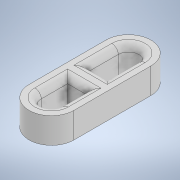
# Autodesk Inventor part: balama_v1
Saved by Autodesk Inventor 2022.6 (Build 266554000, 554)
## iProperties
Created: 2025-08-06
Part Number: balama_v1
Material: Generic
Document SubType Name: Modeling
Designer: Dragos Macovei
Density: 1 g/cm^3
Appearance: Default
Author: Dragos Macovei
Autodesk Inventor part; units mm, degrees
ref_plane "YZ Plane" through (0, 0, 0) normal (1, 0, 0) x (0, 1, 0)
ref_plane "XZ Plane" through (0, 0, 0) normal (0, 1, 0) x (-1, 0, 0)
ref_plane "XY Plane" through (0, 0, 0) normal (0, 0, 1) x (1, 0, 0)
sketch "Sketch1" plane through (0, 0, 0) normal (0, 1, 0) x (-1, 0, 0)
  circle A0 centre (0, 0) radius 1.6
  circle A1 centre (0, -12) radius 1.6
  arc A2 (3.5, 0) -> (-3.5, 0) centre (0, 0) ccw
  arc A3 (-3.5, -12) -> (3.5, -12) centre (0, -12) ccw
  line L0 (3.5, 0) -> (3.5, -12)
  line L1 (-3.5, 0) -> (-3.5, -12)
  dimension "d0" = 3.2
  dimension "d1" = 3.2
  dimension "d2" = 7
  dimension "d3" = 7
  dimension "d4" = 12
  constraints: 4 centre point, 4 end point, 4 point on circle, 3 coincident, 1 parallel, 1 tangent
  measures "d0" diameter of A0
  measures "d1" diameter of A1
  measures "d2" diameter of A2
  measures "d3" diameter of A3
  measures "d4" distance of A1.centre point (0, 0)
extrude "Extrusion1" add sketch "Sketch1" along normal blind 4
sketch "Sketch2" plane through (0, 4, 0) normal (0, 1, 0) x (1, 0, 0)
  circle A0 centre (0, 0) radius 1.6 projected
  line L0 (-1.6, 0) -> (-1.6, 12.1191)
  line L1 (1.6, 0) -> (1.6, 12.1191)
  circle A1 centre (0, 12) radius 1.6 projected
  line L2 (3.5, 0) -> (3.5, 12) projected
  arc A2 (3.5, 12) -> (-3.5, 12) centre (0, 12) ccw projected
  line L3 (-3.5, 12) -> (-3.5, 0) projected
  arc A3 (-3.5, 0) -> (3.5, 0) centre (0, 0) ccw projected
  circle A4 centre (0, 12) radius 1.6 projected
  circle A5 centre (0, 0) radius 1.6 projected
  point P0 (1.6, 12)
  point P1 (-1.6, 12)
  constraints: 4 end point, 2 point on circle, 2 vertical, 1 tangent
extrude "Extrusion2" cut sketch "Sketch2" against normal blind 5 contours A0 L0 A1 L1
sketch "Sketch3" plane through (-1.6, 4, 0) normal (1, 0, 0) x (0, 0, -1)
  point P0 (0, -4)
sketch "Sketch4" plane through (0, 4, 0) normal (0, 1, 0) x (1, 0, 0)
  arc A0 (3.5, 12) -> (-3.5, 12) centre (0, 12) ccw projected
  arc A1 (-3.5, 0) -> (3.5, 0) centre (0, 0) ccw projected
  line L0 (0, -3.5) -> (0, 5.6)
  line L1 (-1.6, 12) -> (-1.6, 0) projected
  line L2 (1.6, 12) -> (1.6, 0) projected
  line L3 (-1.6, 4.1) -> (1.6, 4.1)
  line L4 (1.6, 4.1) -> (1.6, 7.1)
  line L5 (1.6, 7.1) -> (-1.6, 7.1)
  line L6 (-1.6, 7.1) -> (-1.6, 4.1)
  point P0 (0, 15.5)
  point P1 (-1.6, 7.1)
  point P2 (1.6, 4.1)
  dimension "d9" = 19
  dimension "d10" = 9.1
  dimension "d11" = 3
  dimension "d12" = 1.5
  constraints: 10 end point, 2 parallel, 2 point on circle, 2 point on line, 1 horizontal, 1 perpendicular, 1 vertical
  measures "d9" distance of point (0, 15.5) L0.start
  measures "d10" distance of L0.start L0.end
  measures "d11" distance of L4.end L3.end
  measures "d12" distance from line of L5 L0.end
extrude "Extrusion3" add sketch "Sketch4" against normal up to surface (4 mm away)
fillet "Fillet1" radius 1 8 edges at (0, 4, 1.6) (1.6, 4, -2.05) (-1.6, 4, -9.55) (-1.6, 4, -2.05) (0, 4, -13.6) (1.6, 4, -9.55) (0, 4, -7.1) (0, 4, -4.1)
body "Solid1"
